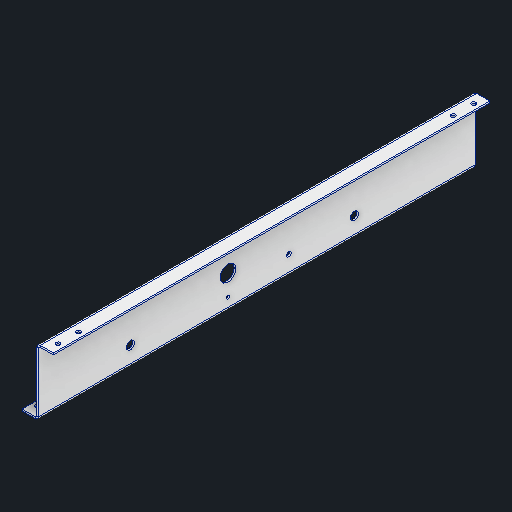
# Autodesk Inventor part: S_Bend
Saved by Autodesk Inventor 2026.2 (Build 302298010, 298A)
## iProperties
Created: 2026-07-08
Part Number: S_Bend
Material: Aluminum 6061
Document SubType Name: Sheet Metal
Designer: User
Density: 2.7 g/cm^3
Sheet Metal Rule: Default_mm
Appearance: Aluminum - Flat
Author: User
Autodesk Inventor part; units mm, degrees
ref_plane "YZ Plane" through (0, 0, 0) normal (1, 0, 0) x (0, 1, 0)
ref_plane "XZ Plane" through (0, 0, 0) normal (0, 1, 0) x (-1, 0, 0)
ref_plane "XY Plane" through (0, 0, 0) normal (0, 0, 1) x (1, 0, 0)
sketch "Sketch2" plane through (0, 0, 0) normal (1, 0, 0) x (0, 1, 0)
  line L0 (0, 0) -> (80, 0)
  line L1 (80, 0) -> (80, -530)
  line L2 (80, -530) -> (0, -530)
  line L3 (0, -530) -> (0, 0)
  dimension "d3" = 80
  dimension "d4" = 530
  measures "d3" distance of L1.end L2.end
  measures "d4" distance of L0.end L1.end
extrude "Plate2" add sketch "Sketch2" along normal blind 2
sketch "Sketch3" plane through (0, 78, 0) normal (0, 1, 0) x (-1, 0, 0)
  line L0 (0, -530) -> (0, 0)
  line L1 (0, 0) -> (-20, 0)
  line L2 (-20, 0) -> (-20, -530)
  line L3 (-20, -530) -> (0, -530)
  constraints: 6 end point, 1 horizontal, 1 perpendicular, 1 vertical
edge flange "Flange1" height 20 angle 90 thickness 2 bend radius 2 thickness toward (0, 1, 0) relief tear relief width 2 relief depth 1 corner gap 2 corner form 0 edges at (2, 80, -265) (0, 0, -265) wall of the first edge with corners at (0, 78, -530) (0, 78, 0) (20, 78, 0) (20, 78, -530)
bend "Bend1"
corner "Corner1"
sketch "Sketch4" plane through (20, 80, 0) normal (0, 1, 0) x (1, 0, 0)
  line L0 (0, 530) -> (0, 0) projected
  line L1 (-16, 530) -> (0, 530) projected
  line L2 (0, 0) -> (-16, 0)
  line L3 (-6.952, 492.5) -> (-6.952, 517.5)
  point P0 (-20, 0)
  point P1 (-6.952, 37.5)
  point P2 (-6.952, 12.5)
  dimension "d101" = 25
  constraints: 4 end point, 2 coincident
  measures "d101" distance of L3.start L3.end
hole "Hole1" at (13.048, 80, -12.5) at (13.048, 80, -37.5) at (13.048, 80, -492.5) at (13.048, 80, -517.5) direction (0, -1, 0) diameter 5.5 end through all
sketch "Sketch5" plane through (-18, 2, 0) normal (0, 1, 0) x (1, 0, 0)
  line L0 (16, 0) -> (0, 0) projected
  line L1 (0, 530) -> (0, 0) projected
  line L2 (16, 0) -> (16, 530) projected
  line L3 (6.5, 13) -> (16, 13)
  line L4 (6.5, 13) -> (6.5, 0)
  line L5 (6.5, 13) -> (6.5, 38)
  line L6 (6.5, 38) -> (6.5, 138)
  line L7 (6.5, 138) -> (6.5, 163)
  line L8 (6.5, 163) -> (6.5, 338)
  line L9 (6.5, 338) -> (6.5, 363)
  line L10 (6.5, 363) -> (6.5, 493)
  line L11 (6.5, 493) -> (6.5, 518)
  line L12 (6.5, 518) -> (6.5, 500)
  point P0 (18, 0)
  dimension "d89" = 9.5
  dimension "d90" = 13
  dimension "d91" = 25
  dimension "d92" = 100
  dimension "d95" = 25
  dimension "d96" = 175
  dimension "d97" = 25
  dimension "d98" = 130
  dimension "d99" = 25
  constraints: 20 end point, 8 coincident, 6 point on line, 3 vertical, 2 perpendicular, 1 collinear
  measures "d89" distance of L3.start L3.end
  measures "d90" distance of L3.start L4.end
  measures "d91" distance of L3.start L5.end
  measures "d92" distance of L5.end L6.end
  measures "d95" distance of L6.end L7.end
  measures "d96" distance of L7.end L8.end
  measures "d97" distance of L8.end L9.end
  measures "d98" distance of L9.end L10.end
  measures "d99" distance of L10.end L11.end
hole "Hole2" at (-11.5, 2, -13) at (-11.5, 2, -38) at (-11.5, 2, -138) at (-11.5, 2, -163) at (-11.5, 2, -338) at (-11.5, 2, -363) at (-11.5, 2, -493) at (-11.5, 2, -518) direction (0, -1, 0) diameter 6.5 end through all
sketch "Sketch6" plane through (0, 0, 0) normal (-1, 0, 0) x (0, 0, 1)
  line L0 (0, 4) -> (0, 76) projected
  line L1 (-230, 40) -> (-230, 65.4)
  line L2 (-230, 65.4) -> (-230, 14.6)
  point P0 (0, 0)
  dimension "d103" = 25.4
  dimension "d104" = 50.8
  constraints: 4 end point, 2 coincident, 1 point on line
  measures "d103" distance of L1.start L1.end
  measures "d104" distance of L1.end L2.end
hole "Hole3" at (0, 65.4, -230) at (0, 14.6, -230) direction (1, 0, 0) diameter 4.04 end through all
sketch "Sketch7" plane through (0, 0, 0) normal (-1, 0, 0) x (0, 0, 1)
  line L0 (0, 4) -> (0, 76) projected
  line L1 (0, 40) -> (-230, 40)
  point P0 (0, 0)
  dimension "d56" = 230
  constraints: 2 end point, 1 coincident, 1 horizontal, 1 midpoint
  measures "d56" distance of L1.start L1.end
hole "Hole4" at (0, 40, -230) direction (1, 0, 0) diameter 19.05 end through all
sketch "Sketch8" plane through (0, 0, 0) normal (-1, 0, 0) x (0, 0, 1)
  line L0 (0, 76) -> (0, 4) projected
  line L1 (-111.5, 40) -> (0, 40)
  line L2 (-530, 76) -> (-530, 4) projected
  line L3 (-530, 40) -> (-383.5, 40)
  line L4 (-530, 0) -> (0, 0) projected
  line L5 (-111.5, 0) -> (-111.5, 23.5)
  line L6 (-383.5, 0) -> (-383.5, 23.5)
  dimension "d85" = 111.5
  dimension "d87" = 146.5
  dimension "d105" = 23.5
  dimension "d106" = 23.5
  constraints: 8 end point, 3 coincident, 2 midpoint, 2 point on line, 1 horizontal, 1 perpendicular
  measures "d85" distance of L1.start L1.end
  measures "d87" distance of L3.start L3.end
  measures "d105" distance of L5.start L5.end
  measures "d106" distance of L6.start L6.end
hole "Hole5" at (0, 23.5, -111.5) at (0, 23.5, -383.5) direction (1, 0, 0) diameter 10 end through all
sketch "Sketch9" plane through (0, 0, 0) normal (-1, 0, 0) x (0, 0, 1)
  line L0 (-530, 0) -> (0, 0) projected
  line L1 (0, 0) -> (0, 23)
  line L2 (0, 0) -> (0, 2) projected
  line L3 (0, 23) -> (-304, 23)
  line L4 (0, 0) -> (0, 64)
  line L5 (-530, 76) -> (0, 76) projected
  line L6 (0, 64) -> (-185, 64)
  dimension "d107" = 23
  dimension "d108" = 304
  dimension "d109" = 64
  dimension "d110" = 185
  constraints: 8 end point, 3 perpendicular, 2 coincident, 1 collinear
  measures "d107" distance of L0.end L1.end
  measures "d108" distance of L1.end L3.end
  measures "d109" distance of L0.end L4.end
  measures "d110" distance of L4.end L6.end
hole "Hole6" at (0, 23, -304) at (0, 64, -185) direction (1, 0, 0) diameter 6 end through all
equation "\"d28\" = Thickness"
equation "\"d116\" = Thickness"
equation "\"d5\" = Thickness"
equation "\"d6\" = BendReliefWidth"
equation "\"d7\" = BendReliefDepth"
equation "\"d8\" = MinimumRemnant"
equation "\"d9\" = TransitionRadius"
equation "\"d12\" = BendRadius"
equation "\"d13\" = CornerReliefSize"
equation "\"d14\" = GapSize"
equation "\"d15\" = JacobiRadiusSize"
equation "\"BendRadius\" = Thickness"
equation "\"BendReliefWidth\" = Thickness"
equation "\"BendReliefDepth\" = 0.5 * Thickness"
equation "\"CornerReliefSize\" = 4 * Thickness"
equation "\"MinimumRemnant\" = 2 * Thickness"
equation "\"TransitionRadius\" = BendRadius"
equation "\"JacobiRadiusSize\" = BendRadius"
equation "\"GapSize\" = Thickness"
equation "\"Thickness\" = 2"
body "Solid2"
